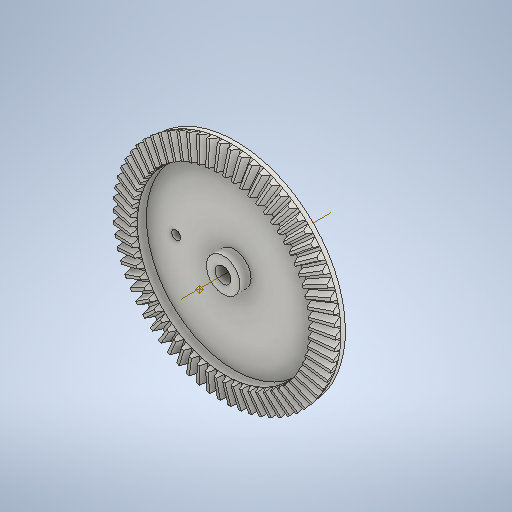
# Autodesk Inventor part: Bevel Gear2
Saved by Autodesk Inventor 2025.2 (Build 292293000, 293)
## iProperties
CustomPartVersion: 1
Created: 2025-03-18
Part Number: Bevel Gear2
Material: Steel, Mild
Document SubType Name: Modeling
Designer: laura
Categories: <?xml version="1.0" encoding="UTF-16"?> <MemberInstance><Categories><FamilyTemplate><FamilyTemplateParameter ValueType="xs:double" Id="1" ObjectReferenceKey="da_z" ObjectType="kUserParameterObject"/><FamilyTemplateParameter ValueType="xs:double" Id="2" ObjectReferenceKey="da_b" ObjectType="kUserParameterObject"/><FamilyTemplateParameter ValueType="xs:double" Id="3" ObjectReferenceKey="da_beta" ObjectType="kUserParameterObject"/><FamilyTemplateParameter ValueType="xs:double" Id="4" ObjectReferenceKey="da_dae" ObjectType="kUserParameterObject"/><FamilyTemplateParameter ValueType="xs:double" Id="5" ObjectReferenceKey="da_ve" ObjectType="kUserParameterObject"/><FamilyTemplateParameter ValueType="xs:double" Id="6" ObjectReferenceKey="da_omega" ObjectType="kUserParameterObject"/><FamilyTemplateParameter ValueType="xs:string" Id="7" ObjectReferenceKey="EAIAABAAAAAAHwAAAAAAAIAAAAAAAAAA" ObjectType="83914240" SubObjectId="SurfaceGeometry"/></FamilyTemplate><ParamToTemplateMap><ParamToTemplate CategoryParameter="//CategoryParameter[@InternalName='046C89C9-8512-4d59-83FE-43B91F4F132A']" TemplateParameter="1"/><ParamToTemplate CategoryParameter="//CategoryParameter[@InternalName='2552DF32-E462-4b46-AEBF-C6C7768E72AC']" TemplateParameter="2"/><ParamToTemplate CategoryParameter="//CategoryParameter[@InternalName='C9EE641D-15FC-4fae-A226-E94C4372FDD7']" TemplateParameter="3"/><ParamToTemplate><ParamToTemplate CategoryParameter="//CategoryParameter[@InternalName='00B6519A-459B-49c7-AD84-2E56D39A5744']" ConstantValue="-0.489724"/></ParamToTemplate><ParamToTemplate><ParamToTemplate CategoryParameter="//CategoryParameter[@InternalName='04B31F0E-C7A6-4894-AA32-9629BEFACF47']" ConstantValue="1.000000"/></ParamToTemplate><ParamToTemplate><ParamToTemplate CategoryParameter="//CategoryParameter[@InternalName='43CBEC2E-7847-49e7-A936-2F7889FCB2D9']" ConstantValue="0.200000"/></ParamToTemplate><ParamToTemplate><ParamToTemplate CategoryParameter="//CategoryParameter[@InternalName='B1EFC894-105D-4ebd-86BF-FA20ED196853']" ConstantValue="0.300000"/></ParamToTemplate><ParamToTemplate><ParamToTemplate CategoryParameter="//CategoryParameter[@InternalName='51175063-3D10-4879-93E8-6246FE8B403D']" ConstantValue="2060000000.000000"/></ParamToTemplate><ParamToTemplate><ParamToTemplate CategoryParameter="//CategoryParameter[@InternalName='A3A52E27-4454-46a9-B0BD-C932399B70AF']" ConstantValue="0.300000"/></ParamToTemplate><ParamToTemplate CategoryParameter="//CategoryParameter[@InternalName='2A200944-5A8C-41ca-B96E-8520D2E510F1']" TemplateParameter="4"/><ParamToTemplate><ParamToTemplate CategoryParameter="//CategoryParameter[@InternalName='1A637F62-92C8-44bc-B81F-10802510B579']" ConstantValue="7.976977"/></ParamToTemplate><ParamToTemplate CategoryParameter="//CategoryParameter[@InternalName='B52DD4BE-6863-48fb-BF58-89EF6F9EC65C']" TemplateParameter="5"/><ParamToTemplate><ParamToTemplate CategoryParameter="//CategoryParameter[@InternalName='3956BFF2-84D2-457d-93C2-9B0613DEBA67']" ConstantValue="0.843444"/></ParamToTemplate><ParamToTemplate CategoryParameter="//CategoryParameter[@InternalName='739CFA02-461B-4bf8-8049-181FCAD8B28F']" TemplateParameter="6"/><ParamToTemplate><ParamToTemplate CategoryParameter="//CategoryParameter[@InternalName='A27E999F-E2CE-4481-8A2A-EBF499C4C3C5']" ConstantValue="-0.045200"/></ParamToTemplate><ParamToTemplate><ParamToTemplate CategoryParameter="//CategoryParameter[@InternalName='9E1B4470-B2D3-4ff1-B813-535BB4CDF51A']" ConstantValue="3520000.000000"/></ParamToTemplate><ParamToTemplate><ParamToTemplate CategoryParameter="//CategoryParameter[@InternalName='F8452263-BFF6-458c-9FB1-07C4B99E95CD']" ConstantValue="11400000.000000"/></ParamToTemplate><ParamToTemplate><ParamToTemplate CategoryParameter="//CategoryParameter[@InternalName='3E3BB259-FD49-497f-8171-6EBC954A3479']" ConstantValue="2.000000"/></ParamToTemplate><ParamToTemplate CategoryParameter="//CategoryParameter[@InternalName='27C3BAF2-7550-4e4b-AE2C-0DB134B7D9B7']" TemplateParameter="7"/></ParamToTemplateMap><Category DisplayName="Gear" InternalName="DC85795E-93AB-48d5-8EEE-5A27447B64BD" Mnemonic="Gear"><CategoryParameter DisplayName="z" InternalName="046C89C9-8512-4d59-83FE-43B91F4F132A" Mnemonic="z"/><CategoryParameter DisplayName="b" InternalName="2552DF32-E462-4b46-AEBF-C6C7768E72AC" Mnemonic="b"/><CategoryParameter DisplayName="||b|" InternalName="C9EE641D-15FC-4fae-A226-E94C4372FDD7" Mnemonic="beta"/><CategoryParameter DisplayName="x" InternalName="00B6519A-459B-49c7-AD84-2E56D39A5744" Mnemonic="x"/><CategoryParameter DisplayName="a*" InternalName="04B31F0E-C7A6-4894-AA32-9629BEFACF47" Mnemonic="a"/><CategoryParameter DisplayName="c*" InternalName="43CBEC2E-7847-49e7-A936-2F7889FCB2D9" Mnemonic="c"/><CategoryParameter DisplayName="r|.f|*" InternalName="B1EFC894-105D-4ebd-86BF-FA20ED196853" Mnemonic="rf"/><CategoryParameter DisplayName="E" InternalName="51175063-3D10-4879-93E8-6246FE8B403D" Mnemonic="E"/><CategoryParameter DisplayName="||m|" InternalName="A3A52E27-4454-46a9-B0BD-C932399B70AF" Mnemonic="mi"/><Category DisplayName="BevelGear" InternalName="0C98F69A-0C2B-4791-B2FE-7691BB227E77" Mnemonic="BevelGear"><CategoryParameter DisplayName="d|.ae|" InternalName="2A200944-5A8C-41ca-B96E-8520D2E510F1" Mnemonic="dae"/><CategoryParameter DisplayName="d|.ai|" InternalName="1A637F62-92C8-44bc-B81F-10802510B579" Mnemonic="dai"/><CategoryParameter DisplayName="A|.e|" InternalName="B52DD4BE-6863-48fb-BF58-89EF6F9EC65C" Mnemonic="ve"/><CategoryParameter DisplayName="A|.i|" InternalName="3956BFF2-84D2-457d-93C2-9B0613DEBA67" Mnemonic="vi"/><CategoryParameter DisplayName="||S|" InternalName="739CFA02-461B-4bf8-8049-181FCAD8B28F" Mnemonic="omega"/><CategoryParameter DisplayName="x|.t|" InternalName="A27E999F-E2CE-4481-8A2A-EBF499C4C3C5" Mnemonic="xt"/><CategoryParameter DisplayName="||s||.Flim|" InternalName="9E1B4470-B2D3-4ff1-B813-535BB4CDF51A" Mnemonic="sFlim"/><CategoryParameter DisplayName="||s||.Hlim|" InternalName="F8452263-BFF6-458c-9FB1-07C4B99E95CD" Mnemonic="sHlim"/><CategoryParameter DisplayName="type" InternalName="3E3BB259-FD49-497f-8171-6EBC954A3479" Mnemonic="type"/><CategoryParameter DisplayName="PitchDiameter" InternalName="27C3BAF2-7550-4e4b-AE2C-0DB134B7D9B7" Mnemonic="IDS_PITCHDIAM"/></Category></Category></Categories></MemberInstance>
Mass: 60.9118 g
Surface Area: 34.3074 cm^2
Volume: 7.7496 cm^3
Density: 7.86 g/cm^3
Appearance: Steel
Author: laura
Autodesk Inventor part; units mm, degrees
(part 1 of 2)
ref_plane "Mesh Plane2" through (0, 0, 0) normal (0.9988673, 0.0475819, 0) x (0, 0, 1)
sketch "Teeth Body Sketch" plane through (0, 0, 0) normal (1, 0, 0) x (0, 1, 0)
  line L0 (0, 0) -> (48.9383, -13.7216) construction
  line L1 (48.9383, -13.7216) -> (49.6696, -10.5036)
  line L2 (49.6696, -10.5036) -> (0, 0) construction
  line L3 (49.5, -11.25) -> (0, 0) construction
  line L4 (39.2976, -11.0185) -> (39.8849, -8.4344)
  line L5 (48.9383, -13.7216) -> (39.2976, -11.0185)
  line L6 (49.6696, -10.5036) -> (39.8849, -8.4344)
  line L7 (0, -16.4659) -> (0, 2.7443) projected
  line L8 (0, -11.25) -> (49.6696, -11.25) construction
  dimension "d0" = 99
  dimension "d1" = 97.8766
  dimension "d2" = 99.3393
  dimension "d3" = 10
  dimension "d4" = 10.5036
  constraints: 16 end point, 4 point on line, 3 perpendicular, 2 collinear, 1 horizontal alignment, 1 vertical alignment
  measures "d0" diameter of L3.start L7
  measures "d1" diameter of L0.end L7
  measures "d2" diameter of L1.end L7
  measures "d3" distance between parallel lines of L1 L4
  measures "d4" vertical distance of L1.end L0.start
revolve "Teeth Body" add sketch "Teeth Body Sketch" angle 360 about axis through (0, 0, 0) along (0, 0, -1)
ref_plane "Tooth Plane" through (0, 49.5, -11.25) normal (0, -0.9751329, 0.2216211) x (1, 0, 0)
sketch "Start Sketch" plane through (0, 49.5, -11.25) normal (0, -0.9751329, 0.2216211) x (1, 0, 0)
  line L0 (0, -268.3768) -> (0, 46.7817) projected
  arc A0 (-0.4737, -2.9306) -> (-2.0874, 1.7457) centre (-71.9073, -24.9644) ccw
  arc A1 (2.0874, 1.7457) -> (0.4737, -2.9306) centre (71.9073, -24.9644) ccw
  line L1 (-0.4737, -2.9306) -> (0.4737, -2.9306)
  arc A2 (2.0874, 1.7457) -> (-2.0874, 1.7457) centre (0, -223.3542) ccw
  dimension "d7" = 74.7546
  dimension "d8" = 71.9073
  dimension "d9" = 198.3898
  dimension "d57" = 225.1096
  dimension "d58" = 220.4236
  constraints: 6 point on circle, 3 centre point, 3 symmetric about line, 2 end point, 1 coincident, 1 perpendicular, 1 other
  measures "d7" radius of A0
  measures "d8" horizontal distance of point (0, -223.354) A0.centre
  measures "d9" vertical distance of point (0, -223.354) A0.centre
  measures "d57" radius of A2
  measures "d58" distance from line of A2.centre L1
sketch "End Sketch" plane through (0, 39.5878, -8.9972) normal (0, -0.9751329, 0.2216211) x (1, 0, 0)
  line L0 (0, -214.6352) -> (0, 37.4138) projected
  arc A0 (-0.3788, -2.3437) -> (-1.6694, 1.3962) centre (-57.5081, -19.9653) ccw
  arc A1 (1.6694, 1.3962) -> (0.3788, -2.3437) centre (57.5081, -19.9653) ccw
  line L1 (-0.3788, -2.3437) -> (0.3788, -2.3437)
  arc A2 (1.6694, 1.3962) -> (-1.6694, 1.3962) centre (0, -178.6282) ccw
  dimension "d12" = 59.7852
  dimension "d15" = 57.5081
  dimension "d16" = 158.6628
  dimension "d59" = 180.0321
  dimension "d60" = 176.2844
  constraints: 6 point on circle, 3 centre point, 3 symmetric about line, 2 end point, 1 coincident, 1 other
  measures "d12" radius of A0
  measures "d15" horizontal distance of A0.centre point (0, -178.628)
  measures "d16" vertical distance of A0.centre point (0, -178.628)
  measures "d59" radius of A2
  measures "d60" distance from line of A2.centre L1
loft "Loft" cut profiles "Start Sketch", "End Sketch"
pattern_circular "Circular Pattern" count 66 over 360 about axis through (0, 0, 0) along (0, 0, 1) of "Loft"
ref_plane "End Plane" through (0, 39.5878, -8.9972) normal (0, -0.9751329, 0.2216211) x (1, 0, 0)
sketch3d "3D Sketch Right"
ref_plane "End Plane Right" through (-3.2784, 39.4518, -8.9972) normal (0.0807547, -0.9717833, 0.2216211) x (0.996565, 0.082814, 0)
sketch "End Sketch Right" plane through (-3.2784, 39.4518, -8.9972) normal (0.0807547, -0.9717833, 0.2216211) x (0.996565, 0.082814, 0)
  arc A0 (-0.3788, -2.3437) -> (-1.6694, 1.3962) centre (-57.5081, -19.9653) ccw
  line L0 (0, -217.5803) -> (0, 40.359) projected
  arc A1 (1.6694, 1.3962) -> (0.3788, -2.3437) centre (57.5081, -19.9653) ccw
  line L1 (-0.3788, -2.3437) -> (0.3788, -2.3437)
  arc A2 (1.6694, 1.3962) -> (-1.6694, 1.3962) centre (0, -178.6282) ccw
  dimension "d70" = 57.5081
  dimension "d71" = 158.6628
  dimension "d72" = 59.7852
  dimension "d73" = 176.2844
  dimension "d74" = 180.0321
  constraints: 6 point on circle, 3 centre point, 3 symmetric about line, 2 end point, 1 coincident, 1 perpendicular, 1 other
  measures "d70" horizontal distance of A2.centre A0.centre
  measures "d71" vertical distance of point (0, -178.628) A0.centre
  measures "d72" radius of A0
  measures "d73" distance from line of point (0, -178.628) L1
  measures "d74" radius of A2
feature "Loft Right" [suppressed]
pattern_circular "Circular Pattern Right" [suppressed]
sketch3d "3D Sketch Left"
ref_plane "End Plane Left" through (3.339, 39.4518, -9.0881) normal (-0.0821969, -0.9711811, 0.2237206) x (0.9964375, -0.0843345, 0)
sketch "End Sketch Left" plane through (3.339, 39.4518, -9.0881) normal (-0.0821969, -0.9711811, 0.2237206) x (0.9964375, -0.0843345, 0)
  line L0 (0, -217.5746) -> (0, 40.5289) projected
  arc A0 (-0.3788, -2.2559) -> (-1.6694, 1.484) centre (-57.5081, -19.8775) ccw
  arc A1 (1.6694, 1.484) -> (0.3788, -2.2559) centre (57.5081, -19.8775) ccw
  line L1 (-0.3788, -2.2559) -> (0.3788, -2.2559)
  ellipse E0 centre (0, -8.2207) end of major axis (39.8849, -8.2207) minor radius 8.9231 projected
  arc A2 (1.6694, 1.484) -> (-1.6694, 1.484) centre (0, -178.5403) ccw
  point P0 (0, -178.5403)
  dimension "d56" = 8.9231
  dimension "d30" = 59.7852
  dimension "d31" = 57.5081
  dimension "d32" = 158.6628
  dimension "d61" = 180.0321
  dimension "d62" = 176.2844
  constraints: 6 point on circle, 3 centre point, 3 symmetric about line, 2 end point, 1 coincident, 2 other
  measures "d30" radius of A0
  measures "d31" horizontal distance of point (0, -178.54) A0.centre
  measures "d32" vertical distance of A0.centre point (0, -178.54)
  measures "d61" radius of A2
  measures "d62" distance from line of point (0, -178.54) L1
feature "Loft Left" [suppressed]
pattern_circular "Circular Pattern Left" [suppressed]
sketch "Body Sketch" plane through (0, 0, 0) normal (1, 0, 0) x (0, 1, 0)
  line L0 (0, -14.2622) -> (0, -10.4778) projected
  line L1 (48.9383, -13.7216) -> (39.2976, -11.0185) projected
  line L2 (39.2976, -11.0185) -> (0, -11.0185)
  line L3 (48.9383, -13.7216) -> (0, -13.7216)
  constraints: 4 end point, 2 perpendicular, 2 point on line
revolve "Fix Body" add sketch "Body Sketch" angle 360 about axis through (0, 0, 0) along (0, 0, 1)
sketch "Sketch6" plane through (0, 0, 0) normal (1, 0, 0) x (0, 1, 0)
  line L0 (49.5, -11.25) -> (0, 0) projected
  line L1 (0, -13.5) -> (0, 2.25) projected
surface revolve "Pitch Diameter" sketch "Sketch6" angle 360 about axis through (0, 0, 0) along (0, 0, 1) shown no curves L0
sketch "Sketch8" plane through (0, 0, -13.7216) normal (0, 0, -1) x (-1, 0, 0)
  arc A0 (-8.6751, -48.1633) -> (-5.2455, -48.6563) centre (0, 0) ccw projected
  arc A1 (-9.8468, -47.9374) -> (-8.6751, -48.1633) centre (0, 0) ccw projected
  arc A2 (-13.214, -47.1205) -> (-9.8468, -47.9374) centre (0, 0) ccw projected
  arc A3 (-14.359, -46.7843) -> (-13.214, -47.1205) centre (0, 0) ccw projected
  arc A4 (-17.6333, -45.6511) -> (-14.359, -46.7843) centre (0, 0) ccw projected
  arc A5 (-18.7411, -45.2076) -> (-17.6333, -45.6511) centre (0, 0) ccw projected
  arc A6 (-21.8928, -43.7683) -> (-18.7411, -45.2076) centre (0, 0) ccw projected
  arc A7 (-22.9535, -43.2214) -> (-21.8928, -43.7683) centre (0, 0) ccw projected
  arc A8 (-25.9541, -41.489) -> (-22.9535, -43.2214) centre (0, 0) ccw projected
  arc A9 (-26.958, -40.8439) -> (-25.9541, -41.489) centre (0, 0) ccw projected
  arc A10 (-29.7804, -38.8341) -> (-26.958, -40.8439) centre (0, 0) ccw projected
  arc A11 (-30.7184, -38.0964) -> (-29.7804, -38.8341) centre (0, 0) ccw projected
  arc A12 (-33.3369, -35.8274) -> (-30.7184, -38.0964) centre (0, 0) ccw projected
  arc A13 (-34.2006, -35.0039) -> (-33.3369, -35.8274) centre (0, 0) ccw projected
  arc A14 (-36.5916, -32.4963) -> (-34.2006, -35.0039) centre (0, 0) ccw projected
  arc A15 (-37.3731, -31.5945) -> (-36.5916, -32.4963) centre (0, 0) ccw projected
  arc A16 (-39.5149, -28.8709) -> (-37.3731, -31.5945) centre (0, 0) ccw projected
  arc A17 (-40.2071, -27.8989) -> (-39.5149, -28.8709) centre (0, 0) ccw projected
  arc A18 (-42.0803, -24.984) -> (-40.2071, -27.8989) centre (0, 0) ccw projected
  arc A19 (-42.677, -23.9506) -> (-42.0803, -24.984) centre (0, 0) ccw projected
  arc A20 (-44.2647, -20.8709) -> (-42.677, -23.9506) centre (0, 0) ccw projected
  arc A21 (-44.7604, -19.7854) -> (-44.2647, -20.8709) centre (0, 0) ccw projected
  arc A22 (-46.0481, -16.5688) -> (-44.7604, -19.7854) centre (0, 0) ccw projected
  arc A23 (-46.4384, -15.4411) -> (-46.0481, -16.5688) centre (0, 0) ccw projected
  arc A24 (-47.4146, -12.1166) -> (-46.4384, -15.4411) centre (0, 0) ccw projected
  arc A25 (-47.6959, -10.9569) -> (-47.4146, -12.1166) centre (0, 0) ccw projected
  arc A26 (-48.3516, -7.5547) -> (-47.6959, -10.9569) centre (0, 0) ccw projected
  arc A27 (-48.5215, -6.3735) -> (-48.3516, -7.5547) centre (0, 0) ccw projected
  arc A28 (-48.8508, -2.9244) -> (-48.5215, -6.3735) centre (0, 0) ccw projected
  arc A29 (-48.9076, -1.7324) -> (-48.8508, -2.9244) centre (0, 0) ccw projected
  arc A30 (-48.9076, 1.7324) -> (-48.9076, -1.7324) centre (0, 0) ccw projected
  arc A31 (-48.8508, 2.9244) -> (-48.9076, 1.7324) centre (0, 0) ccw projected
  arc A32 (-48.5215, 6.3735) -> (-48.8508, 2.9244) centre (0, 0) ccw projected
  arc A33 (-48.3516, 7.5547) -> (-48.5215, 6.3735) centre (0, 0) ccw projected
  arc A34 (-47.6959, 10.9569) -> (-48.3516, 7.5547) centre (0, 0) ccw projected
  arc A35 (-47.4146, 12.1166) -> (-47.6959, 10.9569) centre (0, 0) ccw projected
  arc A36 (-46.4384, 15.4411) -> (-47.4146, 12.1166) centre (0, 0) ccw projected
  arc A37 (-46.0481, 16.5688) -> (-46.4384, 15.4411) centre (0, 0) ccw projected
  arc A38 (-44.7604, 19.7854) -> (-46.0481, 16.5688) centre (0, 0) ccw projected
  arc A39 (-44.2647, 20.8709) -> (-44.7604, 19.7854) centre (0, 0) ccw projected
  arc A40 (-42.677, 23.9506) -> (-44.2647, 20.8709) centre (0, 0) ccw projected
  arc A41 (-42.0803, 24.984) -> (-42.677, 23.9506) centre (0, 0) ccw projected
  arc A42 (-40.2071, 27.8989) -> (-42.0803, 24.984) centre (0, 0) ccw projected
  arc A43 (-39.5149, 28.8709) -> (-40.2071, 27.8989) centre (0, 0) ccw projected
  arc A44 (-37.3731, 31.5945) -> (-39.5149, 28.8709) centre (0, 0) ccw projected
  arc A45 (-36.5916, 32.4963) -> (-37.3731, 31.5945) centre (0, 0) ccw projected
  arc A46 (-34.2006, 35.0039) -> (-36.5916, 32.4963) centre (0, 0) ccw projected
  arc A47 (-33.3369, 35.8274) -> (-34.2006, 35.0039) centre (0, 0) ccw projected
  arc A48 (-30.7184, 38.0964) -> (-33.3369, 35.8274) centre (0, 0) ccw projected
  arc A49 (-29.7804, 38.8341) -> (-30.7184, 38.0964) centre (0, 0) ccw projected
  arc A50 (-26.958, 40.8439) -> (-29.7804, 38.8341) centre (0, 0) ccw projected
  arc A51 (-25.9541, 41.489) -> (-26.958, 40.8439) centre (0, 0) ccw projected
  arc A52 (-22.9535, 43.2214) -> (-25.9541, 41.489) centre (0, 0) ccw projected
  arc A53 (-21.8928, 43.7683) -> (-22.9535, 43.2214) centre (0, 0) ccw projected
  arc A54 (-18.7411, 45.2076) -> (-21.8928, 43.7683) centre (0, 0) ccw projected
  arc A55 (-17.6333, 45.6511) -> (-18.7411, 45.2076) centre (0, 0) ccw projected
  arc A56 (-14.359, 46.7843) -> (-17.6333, 45.6511) centre (0, 0) ccw projected
  arc A57 (-13.214, 47.1205) -> (-14.359, 46.7843) centre (0, 0) ccw projected
  arc A58 (-9.8468, 47.9374) -> (-13.214, 47.1205) centre (0, 0) ccw projected
  arc A59 (-8.6751, 48.1633) -> (-9.8468, 47.9374) centre (0, 0) ccw projected
  arc A60 (-5.2455, 48.6563) -> (-8.6751, 48.1633) centre (0, 0) ccw projected
  arc A61 (-4.0576, 48.7698) -> (-5.2455, 48.6563) centre (0, 0) ccw projected
  arc A62 (-0.5967, 48.9346) -> (-4.0576, 48.7698) centre (0, 0) ccw projected
  arc A63 (0.5967, 48.9346) -> (-0.5967, 48.9346) centre (0, 0) ccw projected
  arc A64 (4.0576, 48.7698) -> (0.5967, 48.9346) centre (0, 0) ccw projected
  arc A65 (5.2455, 48.6563) -> (4.0576, 48.7698) centre (0, 0) ccw projected
  arc A66 (8.6751, 48.1633) -> (5.2455, 48.6563) centre (0, 0) ccw projected
  arc A67 (9.8468, 47.9374) -> (8.6751, 48.1633) centre (0, 0) ccw projected
  arc A68 (13.214, 47.1205) -> (9.8468, 47.9374) centre (0, 0) ccw projected
  arc A69 (14.359, 46.7843) -> (13.214, 47.1205) centre (0, 0) ccw projected
  arc A70 (17.6333, 45.6511) -> (14.359, 46.7843) centre (0, 0) ccw projected
  arc A71 (18.7411, 45.2076) -> (17.6333, 45.6511) centre (0, 0) ccw projected
  arc A72 (21.8928, 43.7683) -> (18.7411, 45.2076) centre (0, 0) ccw projected
  arc A73 (22.9535, 43.2214) -> (21.8928, 43.7683) centre (0, 0) ccw projected
  arc A74 (25.9541, 41.489) -> (22.9535, 43.2214) centre (0, 0) ccw projected
  arc A75 (26.958, 40.8439) -> (25.9541, 41.489) centre (0, 0) ccw projected
  arc A76 (29.7804, 38.8341) -> (26.958, 40.8439) centre (0, 0) ccw projected
  arc A77 (30.7184, 38.0964) -> (29.7804, 38.8341) centre (0, 0) ccw projected
  arc A78 (33.3369, 35.8274) -> (30.7184, 38.0964) centre (0, 0) ccw projected
  arc A79 (34.2006, 35.0039) -> (33.3369, 35.8274) centre (0, 0) ccw projected
  arc A80 (36.5916, 32.4963) -> (34.2006, 35.0039) centre (0, 0) ccw projected
  arc A81 (37.3731, 31.5945) -> (36.5916, 32.4963) centre (0, 0) ccw projected
  arc A82 (39.5149, 28.8709) -> (37.3731, 31.5945) centre (0, 0) ccw projected
  arc A83 (40.2071, 27.8989) -> (39.5149, 28.8709) centre (0, 0) ccw projected
  arc A84 (42.0803, 24.984) -> (40.2071, 27.8989) centre (0, 0) ccw projected
  arc A85 (42.677, 23.9506) -> (42.0803, 24.984) centre (0, 0) ccw projected
  arc A86 (44.2647, 20.8709) -> (42.677, 23.9506) centre (0, 0) ccw projected
  arc A87 (44.7604, 19.7854) -> (44.2647, 20.8709) centre (0, 0) ccw projected
  arc A88 (46.0481, 16.5688) -> (44.7604, 19.7854) centre (0, 0) ccw projected
  arc A89 (46.4384, 15.4411) -> (46.0481, 16.5688) centre (0, 0) ccw projected
  arc A90 (47.4146, 12.1166) -> (46.4384, 15.4411) centre (0, 0) ccw projected
  arc A91 (47.6959, 10.9569) -> (47.4146, 12.1166) centre (0, 0) ccw projected
  arc A92 (48.3516, 7.5547) -> (47.6959, 10.9569) centre (0, 0) ccw projected
  arc A93 (48.5215, 6.3735) -> (48.3516, 7.5547) centre (0, 0) ccw projected
  arc A94 (48.8508, 2.9244) -> (48.5215, 6.3735) centre (0, 0) ccw projected
  arc A95 (48.9076, 1.7324) -> (48.8508, 2.9244) centre (0, 0) ccw projected
  arc A96 (48.9076, -1.7324) -> (48.9076, 1.7324) centre (0, 0) ccw projected
  arc A97 (48.8508, -2.9244) -> (48.9076, -1.7324) centre (0, 0) ccw projected
  arc A98 (48.5215, -6.3735) -> (48.8508, -2.9244) centre (0, 0) ccw projected
  arc A99 (48.3516, -7.5547) -> (48.5215, -6.3735) centre (0, 0) ccw projected
  arc A100 (47.6959, -10.9569) -> (48.3516, -7.5547) centre (0, 0) ccw projected
  arc A101 (47.4146, -12.1166) -> (47.6959, -10.9569) centre (0, 0) ccw projected
  arc A102 (46.4384, -15.4411) -> (47.4146, -12.1166) centre (0, 0) ccw projected
  arc A103 (46.0481, -16.5688) -> (46.4384, -15.4411) centre (0, 0) ccw projected
  arc A104 (44.7604, -19.7854) -> (46.0481, -16.5688) centre (0, 0) ccw projected
  arc A105 (44.2647, -20.8709) -> (44.7604, -19.7854) centre (0, 0) ccw projected
  arc A106 (42.677, -23.9506) -> (44.2647, -20.8709) centre (0, 0) ccw projected
  arc A107 (42.0803, -24.984) -> (42.677, -23.9506) centre (0, 0) ccw projected
  arc A108 (40.2071, -27.8989) -> (42.0803, -24.984) centre (0, 0) ccw projected
  arc A109 (39.5149, -28.8709) -> (40.2071, -27.8989) centre (0, 0) ccw projected
  arc A110 (37.3731, -31.5945) -> (39.5149, -28.8709) centre (0, 0) ccw projected
  arc A111 (36.5916, -32.4963) -> (37.3731, -31.5945) centre (0, 0) ccw projected
  arc A112 (34.2006, -35.0039) -> (36.5916, -32.4963) centre (0, 0) ccw projected
  arc A113 (33.3369, -35.8274) -> (34.2006, -35.0039) centre (0, 0) ccw projected
  arc A114 (30.7184, -38.0964) -> (33.3369, -35.8274) centre (0, 0) ccw projected
  arc A115 (29.7804, -38.8341) -> (30.7184, -38.0964) centre (0, 0) ccw projected
  arc A116 (26.958, -40.8439) -> (29.7804, -38.8341) centre (0, 0) ccw projected
  arc A117 (25.9541, -41.489) -> (26.958, -40.8439) centre (0, 0) ccw projected
  arc A118 (22.9535, -43.2214) -> (25.9541, -41.489) centre (0, 0) ccw projected
  arc A119 (21.8928, -43.7683) -> (22.9535, -43.2214) centre (0, 0) ccw projected
  arc A120 (18.7411, -45.2076) -> (21.8928, -43.7683) centre (0, 0) ccw projected
  arc A121 (17.6333, -45.6511) -> (18.7411, -45.2076) centre (0, 0) ccw projected
  arc A122 (14.359, -46.7843) -> (17.6333, -45.6511) centre (0, 0) ccw projected
  arc A123 (13.214, -47.1205) -> (14.359, -46.7843) centre (0, 0) ccw projected
  arc A124 (9.8468, -47.9374) -> (13.214, -47.1205) centre (0, 0) ccw projected
  arc A125 (8.6751, -48.1633) -> (9.8468, -47.9374) centre (0, 0) ccw projected
  arc A126 (5.2455, -48.6563) -> (8.6751, -48.1633) centre (0, 0) ccw projected
  arc A127 (4.0576, -48.7698) -> (5.2455, -48.6563) centre (0, 0) ccw projected
  arc A128 (0.5967, -48.9346) -> (4.0576, -48.7698) centre (0, 0) ccw projected
  arc A129 (-0.5967, -48.9346) -> (0.5967, -48.9346) centre (0, 0) ccw projected
  arc A130 (-4.0576, -48.7698) -> (-0.5967, -48.9346) centre (0, 0) ccw projected
  arc A131 (-5.2455, -48.6563) -> (-4.0576, -48.7698) centre (0, 0) ccw projected
  circle A132 centre (0, 0) radius 48.9383
  constraints: 1 coincident, 3 other
extrude "Extrusion1" add sketch "Sketch8" along normal blind 2
sketch "Sketch9" plane through (0, 0, 0) normal (0, 1, 0) x (-1, 0, 0)
  line L0 (-48.9383, -15.7216) -> (48.9383, -15.7216) projected
  line L1 (45.9383, -15.7216) -> (45.9383, -17.7216)
  line L2 (15.0492, -11.0185) -> (17.58, -11.0185) projected
  line L3 (14.1596, -11.0185) -> (15.0492, -11.0185) projected
  line L4 (11.5303, -11.0185) -> (14.1596, -11.0185) projected
  line L5 (10.6109, -11.0185) -> (11.5303, -11.0185) projected
  line L6 (7.907, -11.0185) -> (10.6109, -11.0185) projected
  line L7 (6.9661, -11.0185) -> (7.907, -11.0185) projected
  line L8 (4.2121, -11.0185) -> (6.9661, -11.0185) projected
  line L9 (3.2582, -11.0185) -> (4.2121, -11.0185) projected
  line L10 (0.4791, -11.0185) -> (3.2582, -11.0185) projected
  line L11 (-0.4791, -11.0185) -> (0.4791, -11.0185) projected
  line L12 (-3.2582, -11.0185) -> (-0.4791, -11.0185) projected
  line L13 (-4.2121, -11.0185) -> (-3.2582, -11.0185) projected
  line L14 (-6.9661, -11.0185) -> (-4.2121, -11.0185) projected
  line L15 (-7.907, -11.0185) -> (-6.9661, -11.0185) projected
  line L16 (-10.6109, -11.0185) -> (-7.907, -11.0185) projected
  line L17 (-11.5303, -11.0185) -> (-10.6109, -11.0185) projected
  line L18 (-14.1596, -11.0185) -> (-11.5303, -11.0185) projected
  line L19 (-15.0492, -11.0185) -> (-14.1596, -11.0185) projected
  line L20 (-17.58, -11.0185) -> (-15.0492, -11.0185) projected
  line L21 (-18.4317, -11.0185) -> (-17.58, -11.0185) projected
  line L22 (-20.8413, -11.0185) -> (-18.4317, -11.0185) projected
  line L23 (-21.6474, -11.0185) -> (-20.8413, -11.0185) projected
  line L24 (-23.9138, -11.0185) -> (-21.6474, -11.0185) projected
  line L25 (-24.667, -11.0185) -> (-23.9138, -11.0185) projected
  line L26 (-26.7697, -11.0185) -> (-24.667, -11.0185) projected
  line L27 (-27.4632, -11.0185) -> (-26.7697, -11.0185) projected
  line L28 (-29.3832, -11.0185) -> (-27.4632, -11.0185) projected
  line L29 (-30.0107, -11.0185) -> (-29.3832, -11.0185) projected
  line L30 (-31.7306, -11.0185) -> (-30.0107, -11.0185) projected
  line L31 (-32.2864, -11.0185) -> (-31.7306, -11.0185) projected
  line L32 (-33.7906, -11.0185) -> (-32.2864, -11.0185) projected
  line L33 (-34.2698, -11.0185) -> (-33.7906, -11.0185) projected
  line L34 (-35.5447, -11.0185) -> (-34.2698, -11.0185) projected
  line L35 (-35.9427, -11.0185) -> (-35.5447, -11.0185) projected
  line L36 (-36.9768, -11.0185) -> (-35.9427, -11.0185) projected
  line L37 (-37.2902, -11.0185) -> (-36.9768, -11.0185) projected
  line L38 (-38.0741, -11.0185) -> (-37.2902, -11.0185) projected
  line L39 (-38.3, -11.0185) -> (-38.0741, -11.0185) projected
  line L40 (-38.8265, -11.0185) -> (-38.3, -11.0185) projected
  line L41 (-38.9629, -11.0185) -> (-38.8265, -11.0185) projected
  line L42 (-39.2274, -11.0185) -> (-38.9629, -11.0185) projected
  line L43 (-39.273, -11.0185) -> (-39.2274, -11.0185) projected
  line L44 (-39.2976, -11.0185) -> (-39.273, -11.0185) projected
  line L45 (-39.273, -11.0185) -> (-39.2274, -11.0185) projected
  line L46 (-39.2274, -11.0185) -> (-38.9629, -11.0185) projected
  line L47 (-38.9629, -11.0185) -> (-38.8265, -11.0185) projected
  line L48 (-38.8265, -11.0185) -> (-38.3, -11.0185) projected
  line L49 (-38.3, -11.0185) -> (-38.0741, -11.0185) projected
  line L50 (-38.0741, -11.0185) -> (-37.2902, -11.0185) projected
  line L51 (-37.2902, -11.0185) -> (-36.9768, -11.0185) projected
  line L52 (-36.9768, -11.0185) -> (-35.9427, -11.0185) projected
  line L53 (-35.9427, -11.0185) -> (-35.5447, -11.0185) projected
  line L54 (-35.5447, -11.0185) -> (-34.2698, -11.0185) projected
  line L55 (-34.2698, -11.0185) -> (-33.7906, -11.0185) projected
  line L56 (-33.7906, -11.0185) -> (-32.2864, -11.0185) projected
  line L57 (-32.2864, -11.0185) -> (-31.7306, -11.0185) projected
  line L58 (-31.7306, -11.0185) -> (-30.0107, -11.0185) projected
  line L59 (-30.0107, -11.0185) -> (-29.3832, -11.0185) projected
  line L60 (-29.3832, -11.0185) -> (-27.4632, -11.0185) projected
  line L61 (-27.4632, -11.0185) -> (-26.7697, -11.0185) projected
  line L62 (-26.7697, -11.0185) -> (-24.667, -11.0185) projected
  line L63 (-24.667, -11.0185) -> (-23.9138, -11.0185) projected
  line L64 (-23.9138, -11.0185) -> (-21.6474, -11.0185) projected
  line L65 (-21.6474, -11.0185) -> (-20.8413, -11.0185) projected
  line L66 (-20.8413, -11.0185) -> (-18.4317, -11.0185) projected
  line L67 (-18.4317, -11.0185) -> (-17.58, -11.0185) projected
  line L68 (-17.58, -11.0185) -> (-15.0492, -11.0185) projected
  line L69 (-15.0492, -11.0185) -> (-14.1596, -11.0185) projected
  line L70 (-14.1596, -11.0185) -> (-11.5303, -11.0185) projected
  line L71 (-11.5303, -11.0185) -> (-10.6109, -11.0185) projected
  line L72 (-10.6109, -11.0185) -> (-7.907, -11.0185) projected
  line L73 (-7.907, -11.0185) -> (-6.9661, -11.0185) projected
  line L74 (-6.9661, -11.0185) -> (-4.2121, -11.0185) projected
  line L75 (-4.2121, -11.0185) -> (-3.2582, -11.0185) projected
  line L76 (-3.2582, -11.0185) -> (-0.4791, -11.0185) projected
  line L77 (-0.4791, -11.0185) -> (0.4791, -11.0185) projected
  line L78 (0.4791, -11.0185) -> (3.2582, -11.0185) projected
  line L79 (3.2582, -11.0185) -> (4.2121, -11.0185) projected
  line L80 (4.2121, -11.0185) -> (6.9661, -11.0185) projected
  line L81 (6.9661, -11.0185) -> (7.907, -11.0185) projected
  line L82 (7.907, -11.0185) -> (10.6109, -11.0185) projected
  line L83 (10.6109, -11.0185) -> (11.5303, -11.0185) projected
  line L84 (11.5303, -11.0185) -> (14.1596, -11.0185) projected
  line L85 (14.1596, -11.0185) -> (15.0492, -11.0185) projected
  line L86 (15.0492, -11.0185) -> (17.58, -11.0185) projected
  line L87 (17.58, -11.0185) -> (18.4317, -11.0185) projected
  line L88 (18.4317, -11.0185) -> (20.8413, -11.0185) projected
  line L89 (20.8413, -11.0185) -> (21.6474, -11.0185) projected
  line L90 (21.6474, -11.0185) -> (23.9138, -11.0185) projected
  line L91 (23.9138, -11.0185) -> (24.667, -11.0185) projected
  line L92 (24.667, -11.0185) -> (26.7697, -11.0185) projected
  line L93 (26.7697, -11.0185) -> (27.4632, -11.0185) projected
  line L94 (27.4632, -11.0185) -> (29.3832, -11.0185) projected
  line L95 (29.3832, -11.0185) -> (30.0107, -11.0185) projected
  line L96 (30.0107, -11.0185) -> (31.7306, -11.0185) projected
  line L97 (31.7306, -11.0185) -> (32.2864, -11.0185) projected
  line L98 (32.2864, -11.0185) -> (33.7906, -11.0185) projected
  line L99 (33.7906, -11.0185) -> (34.2698, -11.0185) projected
  line L100 (34.2698, -11.0185) -> (35.5447, -11.0185) projected
  line L101 (35.5447, -11.0185) -> (35.9427, -11.0185) projected
  line L102 (35.9427, -11.0185) -> (36.9768, -11.0185) projected
  line L103 (36.9768, -11.0185) -> (37.2902, -11.0185) projected
  line L104 (37.2902, -11.0185) -> (38.0741, -11.0185) projected
  line L105 (38.0741, -11.0185) -> (38.3, -11.0185) projected
  line L106 (38.3, -11.0185) -> (38.8265, -11.0185) projected
  line L107 (38.8265, -11.0185) -> (38.9629, -11.0185) projected
  line L108 (38.9629, -11.0185) -> (39.2274, -11.0185) projected
  line L109 (39.2274, -11.0185) -> (39.273, -11.0185) projected
  line L110 (39.273, -11.0185) -> (39.2976, -11.0185) projected
  line L111 (39.2274, -11.0185) -> (39.273, -11.0185) projected
  line L112 (38.9629, -11.0185) -> (39.2274, -11.0185) projected
  line L113 (38.8265, -11.0185) -> (38.9629, -11.0185) projected
  line L114 (38.3, -11.0185) -> (38.8265, -11.0185) projected
  line L115 (38.0741, -11.0185) -> (38.3, -11.0185) projected
  line L116 (37.2902, -11.0185) -> (38.0741, -11.0185) projected
  line L117 (36.9768, -11.0185) -> (37.2902, -11.0185) projected
  line L118 (35.9427, -11.0185) -> (36.9768, -11.0185) projected
  line L119 (35.5447, -11.0185) -> (35.9427, -11.0185) projected
  line L120 (34.2698, -11.0185) -> (35.5447, -11.0185) projected
  line L121 (33.7906, -11.0185) -> (34.2698, -11.0185) projected
  line L122 (32.2864, -11.0185) -> (33.7906, -11.0185) projected
  line L123 (31.7306, -11.0185) -> (32.2864, -11.0185) projected
  line L124 (30.0107, -11.0185) -> (31.7306, -11.0185) projected
  line L125 (29.3832, -11.0185) -> (30.0107, -11.0185) projected
  line L126 (27.4632, -11.0185) -> (29.3832, -11.0185) projected
  line L127 (26.7697, -11.0185) -> (27.4632, -11.0185) projected
  line L128 (24.667, -11.0185) -> (26.7697, -11.0185) projected
  line L129 (23.9138, -11.0185) -> (24.667, -11.0185) projected
  line L130 (21.6474, -11.0185) -> (23.9138, -11.0185) projected
  line L131 (20.8413, -11.0185) -> (21.6474, -11.0185) projected
  line L132 (18.4317, -11.0185) -> (20.8413, -11.0185) projected
  line L133 (17.58, -11.0185) -> (18.4317, -11.0185) projected
  line L134 (0, -38.6528) -> (0, 6.4421) projected
  line L135 (0, -15.7216) -> (0, -26.2107)
  line L136 (0, -26.2107) -> (0, -32.2107)
  line L137 (6, -26.2107) -> (6, -29.7107)
  line L138 (6, -29.7107) -> (10, -29.7107)
  line L139 (10, -29.7107) -> (10, -32.2107)
  line L140 (10, -32.2107) -> (0, -32.2107)
  line L141 (6, -26.2107) -> (0, -26.2107) construction
  line L142 (45.9383, -17.7216) -> (6, -26.2107)
  line L143 (6, -26.2107) -> (0, -26.2107)
  point P0 (0, 0)
  point P1 (0, -26.2107)
  dimension "d96" = 3
  dimension "d97" = 2
  dimension "d102" = 6
  dimension "d103" = 3.5
  dimension "d104" = 20
  dimension "d105" = 6
  dimension "d132" = 12
  constraints: 21 end point, 5 perpendicular, 3 point on line, 1 collinear, 1 horizontal, 1 midpoint, 1 vertical
  measures "d96" distance from line of L0.end L1
  measures "d97" distance of L1.start L1.end
  measures "d102" distance of L141.end L136.end
  measures "d103" distance of L137.start L137.end
  measures "d104" diameter of L139 L136
  measures "d105" distance of L137.start L141.end
  measures "d132" angle of L141 L142
revolve "Revolution3" add sketch "Sketch9" angle 360 about axis through (0, 0, -15.7216) along (0, 0, -1)
sketch "Sketch14" plane through (0, 0, -11.0185) normal (0, 0, 1) x (1, 0, 0)
  arc A0 (10.6109, 37.838) -> (7.907, 38.4939) centre (0, 0) ccw projected
  arc A1 (7.907, 38.4939) -> (6.9661, 38.6753) centre (0, 0) ccw projected
  arc A2 (6.9661, 38.6753) -> (4.2121, 39.0712) centre (0, 0) ccw projected
  arc A3 (4.2121, 39.0712) -> (3.2582, 39.1623) centre (0, 0) ccw projected
  arc A4 (3.2582, 39.1623) -> (0.4791, 39.2947) centre (0, 0) ccw projected
  arc A5 (0.4791, 39.2947) -> (-0.4791, 39.2947) centre (0, 0) ccw projected
  arc A6 (-0.4791, 39.2947) -> (-3.2582, 39.1623) centre (0, 0) ccw projected
  arc A7 (-3.2582, 39.1623) -> (-4.2121, 39.0712) centre (0, 0) ccw projected
  arc A8 (-4.2121, 39.0712) -> (-6.9661, 38.6753) centre (0, 0) ccw projected
  arc A9 (-6.9661, 38.6753) -> (-7.907, 38.4939) centre (0, 0) ccw projected
  arc A10 (-7.907, 38.4939) -> (-10.6109, 37.838) centre (0, 0) ccw projected
  arc A11 (-10.6109, 37.838) -> (-11.5303, 37.568) centre (0, 0) ccw projected
  arc A12 (-11.5303, 37.568) -> (-14.1596, 36.658) centre (0, 0) ccw projected
  arc A13 (-14.1596, 36.658) -> (-15.0492, 36.3019) centre (0, 0) ccw projected
  arc A14 (-15.0492, 36.3019) -> (-17.58, 35.1461) centre (0, 0) ccw projected
  arc A15 (-17.58, 35.1461) -> (-18.4317, 34.707) centre (0, 0) ccw projected
  arc A16 (-18.4317, 34.707) -> (-20.8413, 33.3158) centre (0, 0) ccw projected
  arc A17 (-20.8413, 33.3158) -> (-21.6474, 32.7978) centre (0, 0) ccw projected
  arc A18 (-21.6474, 32.7978) -> (-23.9138, 31.1839) centre (0, 0) ccw projected
  arc A19 (-23.9138, 31.1839) -> (-24.667, 30.5915) centre (0, 0) ccw projected
  arc A20 (-24.667, 30.5915) -> (-26.7697, 28.7695) centre (0, 0) ccw projected
  arc A21 (-26.7697, 28.7695) -> (-27.4632, 28.1083) centre (0, 0) ccw projected
  arc A22 (-27.4632, 28.1083) -> (-29.3832, 26.0946) centre (0, 0) ccw projected
  arc A23 (-29.3832, 26.0946) -> (-30.0107, 25.3705) centre (0, 0) ccw projected
  arc A24 (-30.0107, 25.3705) -> (-31.7306, 23.1834) centre (0, 0) ccw projected
  arc A25 (-31.7306, 23.1834) -> (-32.2864, 22.4029) centre (0, 0) ccw projected
  arc A26 (-32.2864, 22.4029) -> (-33.7906, 20.0623) centre (0, 0) ccw projected
  arc A27 (-33.7906, 20.0623) -> (-34.2698, 19.2324) centre (0, 0) ccw projected
  arc A28 (-34.2698, 19.2324) -> (-35.5447, 16.7594) centre (0, 0) ccw projected
  arc A29 (-35.5447, 16.7594) -> (-35.9427, 15.8878) centre (0, 0) ccw projected
  arc A30 (-35.9427, 15.8878) -> (-36.9768, 13.3048) centre (0, 0) ccw projected
  arc A31 (-36.9768, 13.3048) -> (-37.2902, 12.3993) centre (0, 0) ccw projected
  arc A32 (-37.2902, 12.3993) -> (-38.0741, 9.7297) centre (0, 0) ccw projected
  arc A33 (-38.0741, 9.7297) -> (-38.3, 8.7985) centre (0, 0) ccw projected
  arc A34 (-38.3, 8.7985) -> (-38.8265, 6.0665) centre (0, 0) ccw projected
  arc A35 (-38.8265, 6.0665) -> (-38.9629, 5.118) centre (0, 0) ccw projected
  arc A36 (-38.9629, 5.118) -> (-39.2274, 2.3483) centre (0, 0) ccw projected
  arc A37 (-39.2274, 2.3483) -> (-39.273, 1.3911) centre (0, 0) ccw projected
  arc A38 (-39.273, 1.3911) -> (-39.273, -1.3911) centre (0, 0) ccw projected
  arc A39 (-39.273, -1.3911) -> (-39.2274, -2.3483) centre (0, 0) ccw projected
  arc A40 (-39.2274, -2.3483) -> (-38.9629, -5.118) centre (0, 0) ccw projected
  arc A41 (-38.9629, -5.118) -> (-38.8265, -6.0665) centre (0, 0) ccw projected
  arc A42 (-38.8265, -6.0665) -> (-38.3, -8.7985) centre (0, 0) ccw projected
  arc A43 (-38.3, -8.7985) -> (-38.0741, -9.7297) centre (0, 0) ccw projected
  arc A44 (-38.0741, -9.7297) -> (-37.2902, -12.3993) centre (0, 0) ccw projected
  arc A45 (-37.2902, -12.3993) -> (-36.9768, -13.3048) centre (0, 0) ccw projected
  arc A46 (-36.9768, -13.3048) -> (-35.9427, -15.8878) centre (0, 0) ccw projected
  arc A47 (-35.9427, -15.8878) -> (-35.5447, -16.7594) centre (0, 0) ccw projected
  arc A48 (-35.5447, -16.7594) -> (-34.2698, -19.2324) centre (0, 0) ccw projected
  arc A49 (-34.2698, -19.2324) -> (-33.7906, -20.0623) centre (0, 0) ccw projected
  arc A50 (-33.7906, -20.0623) -> (-32.2864, -22.4029) centre (0, 0) ccw projected
  arc A51 (-32.2864, -22.4029) -> (-31.7306, -23.1834) centre (0, 0) ccw projected
  arc A52 (-31.7306, -23.1834) -> (-30.0107, -25.3705) centre (0, 0) ccw projected
  arc A53 (-30.0107, -25.3705) -> (-29.3832, -26.0946) centre (0, 0) ccw projected
  arc A54 (-29.3832, -26.0946) -> (-27.4632, -28.1083) centre (0, 0) ccw projected
  arc A55 (-27.4632, -28.1083) -> (-26.7697, -28.7695) centre (0, 0) ccw projected
  arc A56 (-26.7697, -28.7695) -> (-24.667, -30.5915) centre (0, 0) ccw projected
  arc A57 (-24.667, -30.5915) -> (-23.9138, -31.1839) centre (0, 0) ccw projected
  arc A58 (-23.9138, -31.1839) -> (-21.6474, -32.7978) centre (0, 0) ccw projected
  arc A59 (-21.6474, -32.7978) -> (-20.8413, -33.3158) centre (0, 0) ccw projected
  arc A60 (-20.8413, -33.3158) -> (-18.4317, -34.707) centre (0, 0) ccw projected
  arc A61 (-18.4317, -34.707) -> (-17.58, -35.1461) centre (0, 0) ccw projected
  arc A62 (-17.58, -35.1461) -> (-15.0492, -36.3019) centre (0, 0) ccw projected
  arc A63 (-15.0492, -36.3019) -> (-14.1596, -36.658) centre (0, 0) ccw projected
  arc A64 (-14.1596, -36.658) -> (-11.5303, -37.568) centre (0, 0) ccw projected
  arc A65 (-11.5303, -37.568) -> (-10.6109, -37.838) centre (0, 0) ccw projected
  arc A66 (-10.6109, -37.838) -> (-7.907, -38.4939) centre (0, 0) ccw projected
  arc A67 (-7.907, -38.4939) -> (-6.9661, -38.6753) centre (0, 0) ccw projected
  arc A68 (-6.9661, -38.6753) -> (-4.2121, -39.0712) centre (0, 0) ccw projected
  arc A69 (-4.2121, -39.0712) -> (-3.2582, -39.1623) centre (0, 0) ccw projected
  arc A70 (-3.2582, -39.1623) -> (-0.4791, -39.2947) centre (0, 0) ccw projected
  arc A71 (-0.4791, -39.2947) -> (0.4791, -39.2947) centre (0, 0) ccw projected
  arc A72 (0.4791, -39.2947) -> (3.2582, -39.1623) centre (0, 0) ccw projected
  arc A73 (3.2582, -39.1623) -> (4.2121, -39.0712) centre (0, 0) ccw projected
  arc A74 (4.2121, -39.0712) -> (6.9661, -38.6753) centre (0, 0) ccw projected
  arc A75 (6.9661, -38.6753) -> (7.907, -38.4939) centre (0, 0) ccw projected
  arc A76 (7.907, -38.4939) -> (10.6109, -37.838) centre (0, 0) ccw projected
  arc A77 (10.6109, -37.838) -> (11.5303, -37.568) centre (0, 0) ccw projected
  arc A78 (11.5303, -37.568) -> (14.1596, -36.658) centre (0, 0) ccw projected
  arc A79 (14.1596, -36.658) -> (15.0492, -36.3019) centre (0, 0) ccw projected
  arc A80 (15.0492, -36.3019) -> (17.58, -35.1461) centre (0, 0) ccw projected
  arc A81 (17.58, -35.1461) -> (18.4317, -34.707) centre (0, 0) ccw projected
  arc A82 (18.4317, -34.707) -> (20.8413, -33.3158) centre (0, 0) ccw projected
  arc A83 (20.8413, -33.3158) -> (21.6474, -32.7978) centre (0, 0) ccw projected
  arc A84 (21.6474, -32.7978) -> (23.9138, -31.1839) centre (0, 0) ccw projected
  arc A85 (23.9138, -31.1839) -> (24.667, -30.5915) centre (0, 0) ccw projected
  arc A86 (24.667, -30.5915) -> (26.7697, -28.7695) centre (0, 0) ccw projected
  arc A87 (26.7697, -28.7695) -> (27.4632, -28.1083) centre (0, 0) ccw projected
  arc A88 (27.4632, -28.1083) -> (29.3832, -26.0946) centre (0, 0) ccw projected
  arc A89 (29.3832, -26.0946) -> (30.0107, -25.3705) centre (0, 0) ccw projected
  arc A90 (30.0107, -25.3705) -> (31.7306, -23.1834) centre (0, 0) ccw projected
  arc A91 (31.7306, -23.1834) -> (32.2864, -22.4029) centre (0, 0) ccw projected
  arc A92 (32.2864, -22.4029) -> (33.7906, -20.0623) centre (0, 0) ccw projected
  arc A93 (33.7906, -20.0623) -> (34.2698, -19.2324) centre (0, 0) ccw projected
  arc A94 (34.2698, -19.2324) -> (35.5447, -16.7594) centre (0, 0) ccw projected
  arc A95 (35.5447, -16.7594) -> (35.9427, -15.8878) centre (0, 0) ccw projected
  arc A96 (35.9427, -15.8878) -> (36.9768, -13.3048) centre (0, 0) ccw projected
  arc A97 (36.9768, -13.3048) -> (37.2902, -12.3993) centre (0, 0) ccw projected
  arc A98 (37.2902, -12.3993) -> (38.0741, -9.7297) centre (0, 0) ccw projected
  arc A99 (38.0741, -9.7297) -> (38.3, -8.7985) centre (0, 0) ccw projected
  arc A100 (38.3, -8.7985) -> (38.8265, -6.0665) centre (0, 0) ccw projected
  arc A101 (38.8265, -6.0665) -> (38.9629, -5.118) centre (0, 0) ccw projected
  arc A102 (38.9629, -5.118) -> (39.2274, -2.3483) centre (0, 0) ccw projected
  arc A103 (39.2274, -2.3483) -> (39.273, -1.3911) centre (0, 0) ccw projected
  arc A104 (39.273, -1.3911) -> (39.273, 1.3911) centre (0, 0) ccw projected
  arc A105 (39.273, 1.3911) -> (39.2274, 2.3483) centre (0, 0) ccw projected
  arc A106 (39.2274, 2.3483) -> (38.9629, 5.118) centre (0, 0) ccw projected
  arc A107 (38.9629, 5.118) -> (38.8265, 6.0665) centre (0, 0) ccw projected
  arc A108 (38.8265, 6.0665) -> (38.3, 8.7985) centre (0, 0) ccw projected
  arc A109 (38.3, 8.7985) -> (38.0741, 9.7297) centre (0, 0) ccw projected
  arc A110 (38.0741, 9.7297) -> (37.2902, 12.3993) centre (0, 0) ccw projected
  arc A111 (37.2902, 12.3993) -> (36.9768, 13.3048) centre (0, 0) ccw projected
  arc A112 (36.9768, 13.3048) -> (35.9427, 15.8878) centre (0, 0) ccw projected
  arc A113 (35.9427, 15.8878) -> (35.5447, 16.7594) centre (0, 0) ccw projected
  arc A114 (35.5447, 16.7594) -> (34.2698, 19.2324) centre (0, 0) ccw projected
  arc A115 (34.2698, 19.2324) -> (33.7906, 20.0623) centre (0, 0) ccw projected
  arc A116 (33.7906, 20.0623) -> (32.2864, 22.4029) centre (0, 0) ccw projected
  arc A117 (32.2864, 22.4029) -> (31.7306, 23.1834) centre (0, 0) ccw projected
  arc A118 (31.7306, 23.1834) -> (30.0107, 25.3705) centre (0, 0) ccw projected
  arc A119 (30.0107, 25.3705) -> (29.3832, 26.0946) centre (0, 0) ccw projected
  arc A120 (29.3832, 26.0946) -> (27.4632, 28.1083) centre (0, 0) ccw projected
  arc A121 (27.4632, 28.1083) -> (26.7697, 28.7695) centre (0, 0) ccw projected
  arc A122 (26.7697, 28.7695) -> (24.667, 30.5915) centre (0, 0) ccw projected
  arc A123 (24.667, 30.5915) -> (23.9138, 31.1839) centre (0, 0) ccw projected
  arc A124 (23.9138, 31.1839) -> (21.6474, 32.7978) centre (0, 0) ccw projected
  arc A125 (21.6474, 32.7978) -> (20.8413, 33.3158) centre (0, 0) ccw projected
  arc A126 (20.8413, 33.3158) -> (18.4317, 34.707) centre (0, 0) ccw projected
  arc A127 (18.4317, 34.707) -> (17.58, 35.1461) centre (0, 0) ccw projected
  arc A128 (17.58, 35.1461) -> (15.0492, 36.3019) centre (0, 0) ccw projected
  arc A129 (15.0492, 36.3019) -> (14.1596, 36.658) centre (0, 0) ccw projected
  arc A130 (14.1596, 36.658) -> (11.5303, 37.568) centre (0, 0) ccw projected
  arc A131 (11.5303, 37.568) -> (10.6109, 37.838) centre (0, 0) ccw projected
  circle A132 centre (0, 0) radius 39.2976
  constraints: 1 coincident, 3 other
extrude "Extrusion4" cut sketch "Sketch14" against normal blind 4
sketch "Sketch15" plane through (0, 0, 0) normal (0, 1, 0) x (-1, 0, 0)
  line L0 (23.9138, -11.0185) -> (24.667, -11.0185) projected
  line L1 (24.667, -11.0185) -> (26.7697, -11.0185) projected
  line L2 (26.7697, -11.0185) -> (27.4632, -11.0185) projected
  line L3 (27.4632, -11.0185) -> (29.3832, -11.0185) projected
  line L4 (29.3832, -11.0185) -> (30.0107, -11.0185) projected
  line L5 (30.0107, -11.0185) -> (31.7306, -11.0185) projected
  line L6 (31.7306, -11.0185) -> (32.2864, -11.0185) projected
  line L7 (32.2864, -11.0185) -> (33.7906, -11.0185) projected
  line L8 (33.7906, -11.0185) -> (34.2698, -11.0185) projected
  line L9 (34.2698, -11.0185) -> (35.5447, -11.0185) projected
  line L10 (35.5447, -11.0185) -> (35.9427, -11.0185) projected
  line L11 (35.9427, -11.0185) -> (36.9768, -11.0185) projected
  line L12 (36.9768, -11.0185) -> (37.2902, -11.0185) projected
  line L13 (37.2902, -11.0185) -> (38.0741, -11.0185) projected
  line L14 (38.0741, -11.0185) -> (38.3, -11.0185) projected
  line L15 (38.3, -11.0185) -> (38.8265, -11.0185) projected
  line L16 (38.8265, -11.0185) -> (38.9629, -11.0185) projected
  line L17 (38.9629, -11.0185) -> (39.2274, -11.0185) projected
  line L18 (39.2274, -11.0185) -> (39.273, -11.0185) projected
  line L19 (39.273, -11.0185) -> (39.2976, -11.0185) projected
  line L20 (39.2274, -11.0185) -> (39.273, -11.0185) projected
  line L21 (38.9629, -11.0185) -> (39.2274, -11.0185) projected
  line L22 (38.8265, -11.0185) -> (38.9629, -11.0185) projected
  line L23 (38.3, -11.0185) -> (38.8265, -11.0185) projected
  line L24 (38.0741, -11.0185) -> (38.3, -11.0185) projected
  line L25 (37.2902, -11.0185) -> (38.0741, -11.0185) projected
  line L26 (36.9768, -11.0185) -> (37.2902, -11.0185) projected
  line L27 (35.9427, -11.0185) -> (36.9768, -11.0185) projected
  line L28 (35.5447, -11.0185) -> (35.9427, -11.0185) projected
  line L29 (34.2698, -11.0185) -> (35.5447, -11.0185) projected
  line L30 (33.7906, -11.0185) -> (34.2698, -11.0185) projected
  line L31 (32.2864, -11.0185) -> (33.7906, -11.0185) projected
  line L32 (31.7306, -11.0185) -> (32.2864, -11.0185) projected
  line L33 (30.0107, -11.0185) -> (31.7306, -11.0185) projected
  line L34 (29.3832, -11.0185) -> (30.0107, -11.0185) projected
  line L35 (27.4632, -11.0185) -> (29.3832, -11.0185) projected
  line L36 (26.7697, -11.0185) -> (27.4632, -11.0185) projected
  line L37 (24.667, -11.0185) -> (26.7697, -11.0185) projected
  line L38 (23.9138, -11.0185) -> (24.667, -11.0185) projected
  line L39 (21.6474, -11.0185) -> (23.9138, -11.0185) projected
  line L40 (20.8413, -11.0185) -> (21.6474, -11.0185) projected
  line L41 (18.4317, -11.0185) -> (20.8413, -11.0185) projected
  line L42 (17.58, -11.0185) -> (18.4317, -11.0185) projected
  line L43 (15.0492, -11.0185) -> (17.58, -11.0185) projected
  line L44 (14.1596, -11.0185) -> (15.0492, -11.0185) projected
  line L45 (11.5303, -11.0185) -> (14.1596, -11.0185) projected
  line L46 (10.6109, -11.0185) -> (11.5303, -11.0185) projected
  line L47 (7.907, -11.0185) -> (10.6109, -11.0185) projected
  line L48 (6.9661, -11.0185) -> (7.907, -11.0185) projected
  line L49 (4.2121, -11.0185) -> (6.9661, -11.0185) projected
  line L50 (3.2582, -11.0185) -> (4.2121, -11.0185) projected
  line L51 (0.4791, -11.0185) -> (3.2582, -11.0185) projected
  line L52 (-0.4791, -11.0185) -> (0.4791, -11.0185) projected
  line L53 (-3.2582, -11.0185) -> (-0.4791, -11.0185) projected
  line L54 (-4.2121, -11.0185) -> (-3.2582, -11.0185) projected
  line L55 (-6.9661, -11.0185) -> (-4.2121, -11.0185) projected
  line L56 (-7.907, -11.0185) -> (-6.9661, -11.0185) projected
  line L57 (-10.6109, -11.0185) -> (-7.907, -11.0185) projected
  line L58 (-11.5303, -11.0185) -> (-10.6109, -11.0185) projected
  line L59 (-14.1596, -11.0185) -> (-11.5303, -11.0185) projected
  line L60 (-15.0492, -11.0185) -> (-14.1596, -11.0185) projected
  line L61 (-17.58, -11.0185) -> (-15.0492, -11.0185) projected
  line L62 (-18.4317, -11.0185) -> (-17.58, -11.0185) projected
  line L63 (-20.8413, -11.0185) -> (-18.4317, -11.0185) projected
  line L64 (-21.6474, -11.0185) -> (-20.8413, -11.0185) projected
  line L65 (-23.9138, -11.0185) -> (-21.6474, -11.0185) projected
  line L66 (-24.667, -11.0185) -> (-23.9138, -11.0185) projected
  line L67 (-26.7697, -11.0185) -> (-24.667, -11.0185) projected
  line L68 (-27.4632, -11.0185) -> (-26.7697, -11.0185) projected
  line L69 (-29.3832, -11.0185) -> (-27.4632, -11.0185) projected
  line L70 (-30.0107, -11.0185) -> (-29.3832, -11.0185) projected
  line L71 (-31.7306, -11.0185) -> (-30.0107, -11.0185) projected
  line L72 (-32.2864, -11.0185) -> (-31.7306, -11.0185) projected
  line L73 (-33.7906, -11.0185) -> (-32.2864, -11.0185) projected
  line L74 (-34.2698, -11.0185) -> (-33.7906, -11.0185) projected
  line L75 (-35.5447, -11.0185) -> (-34.2698, -11.0185) projected
  line L76 (-35.9427, -11.0185) -> (-35.5447, -11.0185) projected
  line L77 (-36.9768, -11.0185) -> (-35.9427, -11.0185) projected
  line L78 (-37.2902, -11.0185) -> (-36.9768, -11.0185) projected
  line L79 (-38.0741, -11.0185) -> (-37.2902, -11.0185) projected
  line L80 (-38.3, -11.0185) -> (-38.0741, -11.0185) projected
  line L81 (-38.8265, -11.0185) -> (-38.3, -11.0185) projected
  line L82 (-38.9629, -11.0185) -> (-38.8265, -11.0185) projected
  line L83 (-39.2274, -11.0185) -> (-38.9629, -11.0185) projected
  line L84 (-39.273, -11.0185) -> (-39.2274, -11.0185) projected
  line L85 (-39.2976, -11.0185) -> (-39.273, -11.0185) projected
  line L86 (-39.273, -11.0185) -> (-39.2274, -11.0185) projected
  line L87 (-39.2274, -11.0185) -> (-38.9629, -11.0185) projected
  line L88 (-38.9629, -11.0185) -> (-38.8265, -11.0185) projected
  line L89 (-38.8265, -11.0185) -> (-38.3, -11.0185) projected
  line L90 (-38.3, -11.0185) -> (-38.0741, -11.0185) projected
  line L91 (-38.0741, -11.0185) -> (-37.2902, -11.0185) projected
  line L92 (-37.2902, -11.0185) -> (-36.9768, -11.0185) projected
  line L93 (-36.9768, -11.0185) -> (-35.9427, -11.0185) projected
  line L94 (-35.9427, -11.0185) -> (-35.5447, -11.0185) projected
  line L95 (-35.5447, -11.0185) -> (-34.2698, -11.0185) projected
  line L96 (-34.2698, -11.0185) -> (-33.7906, -11.0185) projected
  line L97 (-33.7906, -11.0185) -> (-32.2864, -11.0185) projected
  line L98 (-32.2864, -11.0185) -> (-31.7306, -11.0185) projected
  line L99 (-31.7306, -11.0185) -> (-30.0107, -11.0185) projected
  line L100 (-30.0107, -11.0185) -> (-29.3832, -11.0185) projected
  line L101 (-29.3832, -11.0185) -> (-27.4632, -11.0185) projected
  line L102 (-27.4632, -11.0185) -> (-26.7697, -11.0185) projected
  line L103 (-26.7697, -11.0185) -> (-24.667, -11.0185) projected
  line L104 (-24.667, -11.0185) -> (-23.9138, -11.0185) projected
  line L105 (-23.9138, -11.0185) -> (-21.6474, -11.0185) projected
  line L106 (-21.6474, -11.0185) -> (-20.8413, -11.0185) projected
  line L107 (-20.8413, -11.0185) -> (-18.4317, -11.0185) projected
  line L108 (-18.4317, -11.0185) -> (-17.58, -11.0185) projected
  line L109 (-17.58, -11.0185) -> (-15.0492, -11.0185) projected
  line L110 (-15.0492, -11.0185) -> (-14.1596, -11.0185) projected
  line L111 (-14.1596, -11.0185) -> (-11.5303, -11.0185) projected
  line L112 (-11.5303, -11.0185) -> (-10.6109, -11.0185) projected
  line L113 (-10.6109, -11.0185) -> (-7.907, -11.0185) projected
  line L114 (-7.907, -11.0185) -> (-6.9661, -11.0185) projected
  line L115 (-6.9661, -11.0185) -> (-4.2121, -11.0185) projected
  line L116 (-4.2121, -11.0185) -> (-3.2582, -11.0185) projected
  line L117 (-3.2582, -11.0185) -> (-0.4791, -11.0185) projected
  line L118 (-0.4791, -11.0185) -> (0.4791, -11.0185) projected
  line L119 (0.4791, -11.0185) -> (3.2582, -11.0185) projected
  line L120 (3.2582, -11.0185) -> (4.2121, -11.0185) projected
  line L121 (4.2121, -11.0185) -> (6.9661, -11.0185) projected
  line L122 (6.9661, -11.0185) -> (7.907, -11.0185) projected
  line L123 (7.907, -11.0185) -> (10.6109, -11.0185) projected
  line L124 (10.6109, -11.0185) -> (11.5303, -11.0185) projected
  line L125 (11.5303, -11.0185) -> (14.1596, -11.0185) projected
  line L126 (14.1596, -11.0185) -> (15.0492, -11.0185) projected
  line L127 (15.0492, -11.0185) -> (17.58, -11.0185) projected
  line L128 (17.58, -11.0185) -> (18.4317, -11.0185) projected
  line L129 (18.4317, -11.0185) -> (20.8413, -11.0185) projected
  line L130 (20.8413, -11.0185) -> (21.6474, -11.0185) projected
  line L131 (21.6474, -11.0185) -> (23.9138, -11.0185) projected
  line L132 (-39.2976, -15.0185) -> (39.2976, -15.0185) projected
  line L133 (-7.5, -15.0185) -> (-7.5, -10.0185)
  line L134 (-6, -26.2107) -> (6, -26.2107) projected
  line L135 (-6, -29.7107) -> (6, -29.7107) projected
  line L136 (-6, -26.2107) -> (-6, -29.7107) projected
  line L137 (6, -26.2107) -> (6, -29.7107) projected
  line L138 (-7.5, -10.0185) -> (0, -10.0185)
  line L139 (0, -35.6528) -> (0, 5.9421) projected
  point P0 (0, 0)
  point P1 (0, -15.0185)
  dimension "d124" = 5
  dimension "d134" = 15
  constraints: 4 end point, 2 point on line, 1 horizontal, 1 perpendicular
  measures "d124" distance between parallel lines of L132 L138
  measures "d134" diameter of L133 L139
revolve "Revolution7" add sketch "Sketch15" angle 360 about axis through (0, 0, 0) along (0, 0, 1) contours L53 L54 L55 L56 L133 L138 L139 L52 | L52 L139 L132 L133 L56 L55 L54 L53
sketch "Sketch16" plane through (0, 0, -10.0185) normal (0, 0, 1) x (1, 0, 0)
  circle A0 centre (0, 0) radius 3.5
  circle A1 centre (-26, 0) radius 2
  line L0 (0, 0) -> (-26, 0) construction
  dimension "d126" = 7
  dimension "d127" = 4
  dimension "d129" = 26
  constraints: 2 centre point, 2 coincident, 2 end point, 1 horizontal
  measures "d126" diameter of A0
  measures "d127" diameter of A1
  measures "d129" distance of L0.start L0.end
extrude "Extrusion5" cut sketch "Sketch16" against normal through all
equation "\"d0\" = da_de"
equation "\"d1\" = da_dfe"
equation "\"d2\" = da_dae"